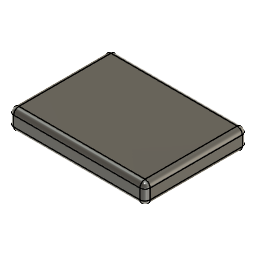
Music Player Assembly (Autodesk Fusion 360 archive; units mm, degrees)
design "Battery"
part number: 2026-08-27-20-13-11-327
Autodesk Fusion 360 part; units mm, degrees
sketch "Sketch1" plane through (0, 0, 0) normal (0, 0, 1) x (1, 0, 0)
  line L0 (13, 11) -> (-27, 11)
  line L1 (-27, 11) -> (-27, -19)
  line L2 (-27, -19) -> (13, -19)
  line L3 (13, -19) -> (13, 11)
  dimension "d1" = 40
  dimension "d2" = 30
  constraint horizontal L0
  constraint vertical L1
  constraint horizontal L2
  constraint vertical L3
  measures "d1" distance of L0.start L0.end
  measures "d2" distance of L0.start L2.end
extrude "Extrude1" add sketch "Sketch1" along normal blind 6
fillet "Fillet1" radius 1.5 4 edges at (-7, 11, 6) (-27, -4, 6) (-7, -19, 6) (13, -4, 6)
fillet "Fillet2" radius 1.5 12 edges at (13, -19, 2.25) (12.5607, -18.5607, 5.5607) (13, -4, 0) (-7, -19, 0) (-27, -19, 2.25) (-26.5607, -18.5607, 5.5607) (-27, -4, 0) (-27, 11, 2.25) (-26.5607, 10.5607, 5.5607) (13, 11, 2.25) (12.5607, 10.5607, 5.5607) (-7, 11, 0)
